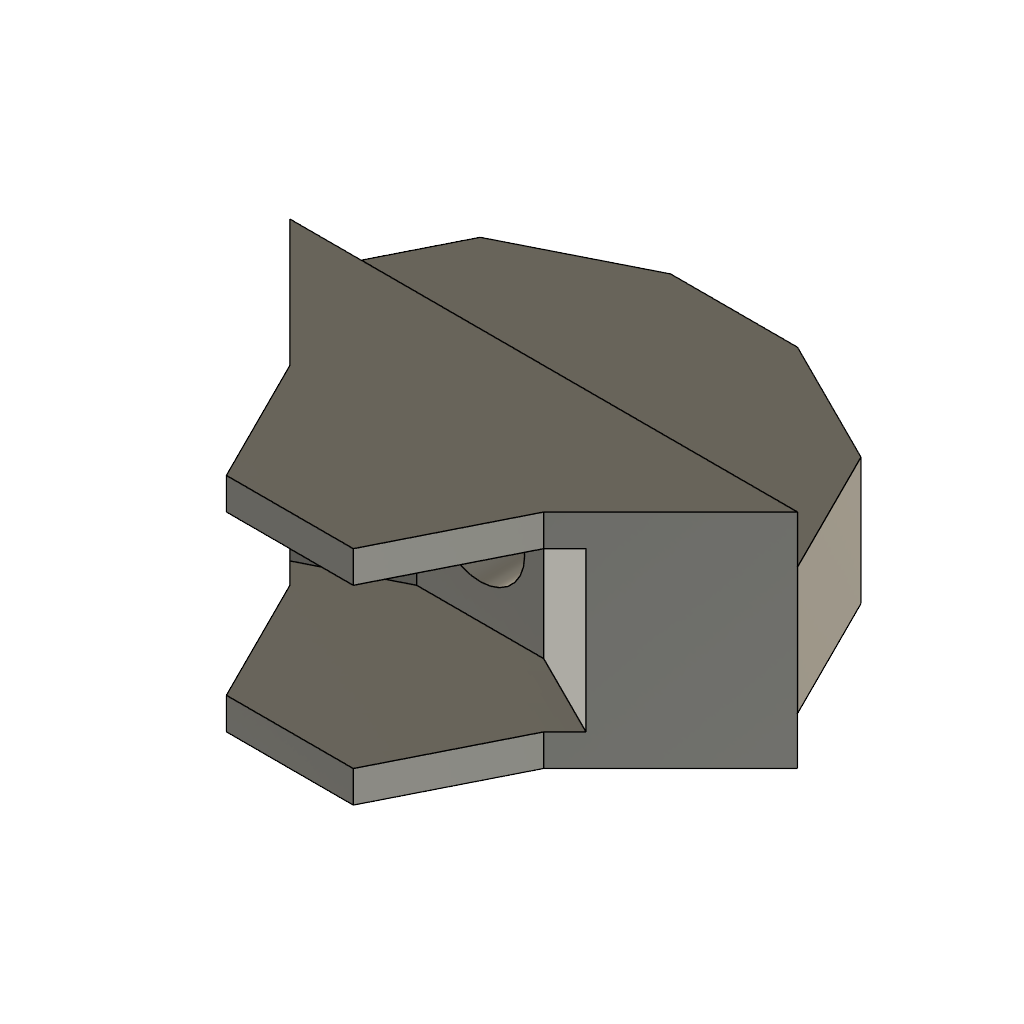
pieza_3 (Autodesk Fusion 360 design; units mm, degrees)
part number: 2026-11-08-08-23-51-412
Autodesk Fusion 360 part; units mm, degrees
sketch "Boceto1" plane through (0, 0, 0) normal (0, 0, 1) x (1, 0, 0)
  line L0 (0, 0) -> (40, 0)
  line L1 (40, 0) -> (30, -10)
  line L2 (0, 0) -> (10, -10)
  line L3 (30, -10) -> (25, -20)
  line L4 (10, -10) -> (15, -20)
  line L5 (25, -20) -> (15, -20)
  dimension "d1" = 40
  constraint coincident L0.start L2.start
  constraint horizontal L0
  measures "d1" distance of L0.start L0.end
extrude "Extruir1" add sketch "Boceto1" along normal blind 2.5 makes body 1
copy_body "CopiarPegarCuerpos1" bodies 1 makes body 2
move_body "Desplazar1" bodies 2 to x (1, 0, 0) y (0, 1, 0) z (0, 0, 1) at (0, 0, 15)
sketch "Boceto2" plane through (0, 0, 2.5) normal (0, 0, 1) x (-1, 0, 0)
  line L0 (0, 0) -> (-10, 10)
  line L1 (-10, 10) -> (-15, 20)
  line L2 (-15, 20) -> (-25, 20)
  line L3 (-25, 20) -> (-30, 10)
  line L4 (-30, 10) -> (-40, 0)
  line L5 (-40, 0) -> (0, 0)
  line L6 (-15, 5) -> (-25, 5)
  line L7 (-25, 5) -> (-31.6667, 8.3333)
  line L8 (-15, 5) -> (-8.3333, 8.3333)
  line L9 (0, 0) -> (-40, 0)
  line L10 (-31.6667, 8.3333) -> (-40, 0)
  line L11 (-8.3333, 8.3333) -> (0, 0)
  constraint coincident L4 L7.end
  constraint coincident L0 L8.end
  constraint coincident L0.start L5.end
  constraint coincident L4.end L5.start
extrude "Extruir2" add sketch "Boceto2" along normal blind 12.5 contours L0 L4 L5 L6 L7 L8 L9 L10 L11 bodies 1 2
sketch "Boceto3" plane through (0, 0, 0) normal (0, 0, 1) x (1, 0, 0)
sketch "Boceto4" plane through (0, 0, 0) normal (0, 0, 1) x (1, 0, 0)
  line L0 (40, 0, 3.75) -> (0, 0, 3.75)
  line L1 (4.9634, 9.886, 3.7028) -> (14.9634, 14.886, 3.7028)
  line L2 (14.9634, 14.886, 3.7028) -> (24.9634, 14.886, 3.7028)
  line L3 (24.9634, 14.886, 3.7028) -> (34.9634, 9.886, 3.7028)
  line L4 (34.9634, 9.886, 3.7028) -> (40, 0, 3.75)
  line L5 (0, 0, 3.75) -> (4.9634, 9.886, 3.7028)
  line L6 (40, 5) -> (0, 5)
  line L7 (0, 5) -> (5, 15)
  line L8 (40, 5) -> (35, 15)
  line L9 (35, 15) -> (25, 20)
  line L10 (25, 20) -> (15, 20)
  line L11 (15, 20) -> (5, 15)
  point P0 (40, 0)
  constraint horizontal L6
  constraint parallel L6 L10
extrude "Extruir3" add sketch "Boceto4" along normal blind 10 separate body makes body 3
move_body "Desplazar2" bodies 3 to x (1, 0, 0) y (0, 1, 0) z (0, 0, 1) at (0, -5, 3.75)
hole "Agujero1" at (20, -5, 8.75) direction (0, 1, 0) diameter 7 depth 8 tip angle 180 bodies 1 3
hole "Agujero2" at (20, 15, 8.75) direction (0, -1, 0) diameter 7 depth 8 tip angle 180 bodies 3
hole "Agujero3" at (10, 12.5, 8.75) direction (0.447214, -0.894427, 0) diameter 7 depth 8 tip angle 180 bodies 3
hole "Agujero4" at (30, 12.5, 8.75) direction (-0.447214, -0.894427, 0) diameter 7 depth 8 tip angle 180 bodies 3
